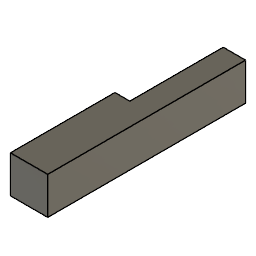
Left Fake Cross Base Beam (Autodesk Fusion 360 design; units mm, degrees)
Autodesk Fusion 360 part; units mm, degrees
sketch "Sketch1" plane through (0, 0, 0) normal (1, 0, 0) x (0, 1, 0)
  circle A0 centre (0, 0) radius 2.1971
  circle A1 centre (25.4, 0) radius 2.1971
  line L0 (10.16, 2.54) -> (15.24, 2.54)
  line L1 (15.24, 2.54) -> (15.24, -2.54)
  line L2 (15.24, -2.54) -> (10.16, -2.54)
  line L3 (10.16, -2.54) -> (10.16, 2.54)
  line L4 (-6.35, 4.7625) -> (31.75, 4.7625)
  line L5 (31.75, 4.7625) -> (31.75, -4.7625)
  line L6 (31.75, -4.7625) -> (-6.35, -4.7625)
  line L7 (-6.35, -4.7625) -> (-6.35, 4.7625)
  dimension "d1" = 25.4
  dimension "d2" = 4.3942
  dimension "d3" = 4.3942
  dimension "d4" = 5.08
  dimension "d5" = 5.08
  dimension "d6" = 2.54
  dimension "d7" = 10.16
  dimension "d8" = 9.525
  dimension "d9" = 38.1
  dimension "d10" = 4.7625
  dimension "d11" = 6.35
  constraint horizontal A0.centre A1.centre
  constraint horizontal L0
  constraint vertical L1
  constraint horizontal L2
  constraint vertical L3
  constraint coincident A0.centre origin
  constraint horizontal L4
  constraint vertical L5
  constraint horizontal L6
  constraint vertical L7
  measures "d1" distance of A0.centre A1.centre
  measures "d2" diameter of A0
  measures "d3" diameter of A1
  measures "d4" distance of L0.start L0.end
  measures "d5" distance of L0.start L2.end
  measures "d6" distance of A0.centre L0
  measures "d7" horizontal distance of A0.centre L2.end
  measures "d8" distance of L4.start L6.end
  measures "d9" distance of L4.start L4.end
  measures "d10" distance of A0.centre L4
  measures "d11" distance of A0.centre L7
extrude "Extrude1" add sketch "Sketch1" along normal blind 2.54 contours A0 | A1 | L0 L1 L2 L3 | L4 L5 L6 L7
sketch "Sketch2" plane through (2.54, 0, 0) normal (1, 0, 0) x (0, 1, 0)
  line L0 (-6.35, -4.7625) -> (31.75, -4.7625)
  line L1 (31.75, -4.7625) -> (31.75, 4.7625)
  line L2 (31.75, 4.7625) -> (-6.35, 4.7625)
  line L3 (-6.35, 4.7625) -> (-6.35, -4.7625)
  line L4 (31.75, 4.7625) -> (-6.35, 4.7625)
  line L5 (-6.35, 4.7625) -> (-6.35, -4.7625)
  line L6 (-6.35, -4.7625) -> (31.75, -4.7625)
  line L7 (31.75, -4.7625) -> (31.75, 4.7625)
  circle A0 centre (0, 0) radius 2.1971
  circle A1 centre (25.4, 0) radius 2.1971
  dimension "d14" = 4.3942
  dimension "d15" = 4.3942
  constraint horizontal L4
  constraint vertical L5
  constraint horizontal L6
  constraint vertical L7
  constraint coincident L0.start L3.end
  constraint coincident L1.end L2.start
  measures "d14" diameter of A0
  measures "d15" diameter of A1
extrude "Extrude2" add sketch "Sketch2" along normal blind 3.81 contours L0 L1 L2 L3 L4 L5 L6 L7 | A0 | A1
sketch "Sketch3" plane through (0, -6.35, 0) normal (0, -1, 0) x (1, 0, 0)
  line L0 (0, 4.7625) -> (0, -4.7625)
  line L1 (0, -4.7625) -> (6.35, -4.7625)
  line L2 (6.35, -4.7625) -> (6.35, 4.7625)
  line L3 (6.35, 4.7625) -> (0, 4.7625)
  line L4 (0, 4.7625) -> (6.35, 4.7625)
  line L5 (6.35, 4.7625) -> (6.35, -4.7625)
  line L6 (6.35, -4.7625) -> (0, -4.7625)
  line L7 (0, -4.7625) -> (0, 4.7625)
  constraint horizontal L4
  constraint vertical L5
  constraint horizontal L6
  constraint vertical L7
  constraint coincident L1.end L2.start
  constraint coincident L0.start L3.end
extrude "Extrude3" add sketch "Sketch3" along normal blind 127
sketch "Sketch4" plane through (6.35, 0, 0) normal (1, 0, 0) x (0, 1, 0)
  line L0 (31.75, -4.7625) -> (31.75, 4.7625)
  line L1 (31.75, 4.7625) -> (-133.35, 4.7625)
  line L2 (-133.35, 4.7625) -> (-133.35, -4.7625)
  line L3 (-133.35, -4.7625) -> (31.75, -4.7625)
  circle A0 centre (-47.625, 1.5875) radius 1.6
  circle A1 centre (-22.225, 1.5875) radius 1.6
  dimension "d22" = 3.2
  dimension "d23" = 3.2
  dimension "d27" = 6.35
  dimension "d62" = 25.4
  constraint horizontal A0.centre A1.centre
  measures "d22" diameter of A0
  measures "d23" diameter of A1
  measures "d27" distance of L3 A1.centre
  measures "d62" distance of A0.centre A1.centre
sketch "Sketch6" plane through (0, -133.35, 0) normal (0, -1, 0) x (1, 0, 0)
  line L0 (0, -4.7625) -> (6.35, -4.7625)
  line L1 (6.35, -4.7625) -> (6.35, 4.7625)
  line L2 (6.35, 4.7625) -> (0, 4.7625)
  line L3 (0, 4.7625) -> (0, -4.7625)
  line L4 (0, 4.7625) -> (6.35, 4.7625)
  line L5 (6.35, 4.7625) -> (6.35, -1.5875)
  line L6 (6.35, -1.5875) -> (0, -1.5875)
  line L7 (0, -1.5875) -> (0, 4.7625)
  dimension "d29" = 6.35
  dimension "d30" = 6.35
  constraint horizontal L4
  constraint vertical L5
  constraint horizontal L6
  constraint vertical L7
  constraint coincident L2.end L3.start
  measures "d29" distance of L2.end L1.end
  measures "d30" distance of L2.end L6.end
extrude "Extrude5" cut sketch "Sketch6" against normal blind 67.945 contours L0 L1 L3 L6
sketch "Sketch7" plane through (0, 0, 0) normal (-1, 0, 0) x (0, -1, 0)
  line L0 (65.405, -4.7625) -> (65.405, -1.5875)
  line L1 (65.405, -1.5875) -> (133.35, -1.5875)
  line L2 (133.35, -1.5875) -> (133.35, 4.7625)
  line L3 (133.35, 4.7625) -> (-31.75, 4.7625)
  line L4 (-31.75, 4.7625) -> (-31.75, -4.7625)
  line L5 (-31.75, -4.7625) -> (65.405, -4.7625)
  circle A0 centre (117.475, 1.5875) radius 2.1
  dimension "d33" = 4.2
  dimension "d34" = 3.175
  dimension "d35" = 15.875
  measures "d33" diameter of A0
  measures "d34" distance of L3 A0.centre
  measures "d35" distance of L2 A0.centre
extrude "Extrude6" cut sketch "Sketch7" against normal blind 6.35 contours A0
sketch "Sketch8" plane through (0, 0, 0) normal (-1, 0, 0) x (0, -1, 0)
  circle A0 centre (117.475, 1.5875) radius 2.1
  line L0 (65.405, -4.7625) -> (65.405, -1.5875)
  line L1 (65.405, -1.5875) -> (133.35, -1.5875)
  line L2 (133.35, -1.5875) -> (133.35, 4.7625)
  line L3 (133.35, 4.7625) -> (-31.75, 4.7625)
  line L4 (-31.75, 4.7625) -> (-31.75, -4.7625)
  line L5 (-31.75, -4.7625) -> (65.405, -4.7625)
  circle A1 centre (117.475, 11.4427) radius 2.1
  circle A2 centre (117.475, 11.4427) radius 3.175
  circle A3 centre (106.045, 11.4427) radius 2.1
  circle A4 centre (106.045, 11.4427) radius 3.175
  line L6 (117.475, 8.2677) -> (106.045, 8.2677)
  line L7 (117.475, 14.6177) -> (106.045, 14.6177)
  line L8 (106.045, 14.6177) -> (70.9402, 14.6177)
  line L9 (70.9402, 14.6177) -> (65.405, 6.5046)
  line L10 (106.045, 8.2677) -> (74.295, 8.2677)
  line L11 (74.295, 8.2677) -> (65.405, -4.7625)
  line L12 (65.405, 6.5046) -> (65.405, -4.7625)
  line L13 (65.405, 6.5046) -> (64.2164, 4.7625)
  line L14 (120.65, 8.2677) -> (102.87, 8.2677)
  line L15 (102.87, 8.2677) -> (102.87, 14.6177)
  line L16 (102.87, 14.6177) -> (120.65, 14.6177)
  line L17 (120.65, 14.6177) -> (120.65, 8.2677)
  dimension "d38" = 4.2
  dimension "d39" = 9.8552
  dimension "d40" = 6.35
  dimension "d45" = 4.2
  dimension "d46" = 6.35
  dimension "d47" = 11.43
  dimension "d66" = 6.35
  dimension "d68" = 31.75
  dimension "d69" = 6.35
  constraint vertical A0.centre A1.centre
  constraint concentric A1 A2
  constraint concentric A3 A4
  constraint horizontal A1.centre A3.centre
  constraint coincident A2 L6.start
  constraint coincident A4 L6.end
  constraint coincident A2 L7.start
  constraint coincident A4 L7.end
  constraint tangent A4 L7
  constraint horizontal L6
  constraint horizontal L7
  constraint parallel L7 L8
  constraint parallel L3 L10
  constraint coincident L0.start L5.end
  constraint parallel L9 L11
  constraint vertical L9.end L0.start
  constraint coincident L3 L13.end
  constraint parallel L9 L13
  constraint horizontal L14
  constraint vertical L15
  constraint horizontal L16
  constraint vertical L17
  constraint coincident L8 L15.end
  constraint coincident L10 L14.end
  constraint tangent A2 L17
  constraint tangent A4 L15
  measures "d38" diameter of A1
  measures "d39" vertical distance of A0.centre A1.centre
  measures "d40" diameter of A2
  measures "d45" diameter of A3
  measures "d46" diameter of A4
  measures "d47" distance of A1.centre A3.centre
  measures "d66" distance of L8 L10
  measures "d68" distance of L6.end L10.end
  measures "d69" distance of L9 L11
extrude "Extrude7" cut sketch "Sketch8" against normal blind 6.35 contours L0 L1 L11 L12 | L1 L2 L3 L11
extrude "Extrude8" add sketch "Sketch8" along normal blind -6.35 and the other way blind 2.54 contours L0 L1 L11 L12 | L1 L3 L11 L12 | L3 L8 L9 L10 L11 L12 L15 | L3 L12 L13 | A4 L10 L14 L15 | A4 L8 L15 L16 | A4 | A2 A4 L6 L7 L14 L16 | A2 | A2 L14 L17 | A2 L16 L17 | A1 | A3
extrude "Extrude9" add sketch "Sketch8" against normal blind 2.54 contours L0 L1 L11 L12 | A4 L10 L14 L15 | A4 L8 L15 L16 | A4 | A2 A4 L6 L7 L14 L16 | A2 | A2 L14 L17 | A2 L16 L17 | A1 | A3
sketch "Sketch10" plane through (0, 0, -4.7625) normal (0, 0, -1) x (1, 0, 0)
  line L0 (6.35, 65.405) -> (0, 65.405)
  line L1 (0, 65.405) -> (0, -31.75)
  line L2 (0, -31.75) -> (6.35, -31.75)
  line L3 (6.35, -31.75) -> (6.35, 65.405)
  line L4 (6.35, -31.75) -> (0, -31.75)
  line L5 (0, -31.75) -> (0, 65.405)
  line L6 (0, 65.405) -> (6.35, 65.405)
  line L7 (6.35, 65.405) -> (6.35, -31.75)
  constraint horizontal L4
  constraint vertical L5
  constraint horizontal L6
  constraint vertical L7
  constraint coincident L0.end L1.start
  constraint coincident L2.end L3.start
extrude "Extrude12" add sketch "Sketch10" along normal blind 0.4318
sketch "Sketch11" plane through (0, 31.75, 0) normal (0, 1, 0) x (-1, 0, 0)
  line L0 (0, -5.1943) -> (0, 4.7625)
  line L1 (0, 4.7625) -> (-6.35, 4.7625)
  line L2 (-6.35, 4.7625) -> (-6.35, -5.1943)
  line L3 (-6.35, -5.1943) -> (0, -5.1943)
  line L4 (0, -5.1943) -> (-6.35, -5.1943)
  line L5 (-6.35, -5.1943) -> (-6.35, 4.7625)
  line L6 (-6.35, 4.7625) -> (0, 4.7625)
  line L7 (0, 4.7625) -> (0, -5.1943)
  constraint horizontal L4
  constraint vertical L5
  constraint horizontal L6
  constraint vertical L7
  constraint coincident L1.end L2.start
  constraint coincident L0.start L3.end
extrude "Extrude13" add sketch "Sketch11" along normal blind 12.7
sketch "Sketch12" plane through (0, 0, 4.7625) normal (0, 0, 1) x (-1, 0, 0)
  line L0 (-2.54, 64.2164) -> (-6.35, 64.2164)
  line L1 (-6.35, 64.2164) -> (-6.35, -44.45)
  line L2 (-6.35, -44.45) -> (0, -44.45)
  line L3 (0, -44.45) -> (0, 71.9035)
  line L4 (0, 71.9035) -> (-2.54, 71.9035)
  line L5 (-2.54, 71.9035) -> (-2.54, 64.2164)
  line L6 (0, -44.45) -> (-6.35, -44.45)
  line L7 (-6.35, -44.45) -> (-6.35, 6.35)
  line L8 (-6.35, 6.35) -> (0, 6.35)
  line L9 (0, 6.35) -> (0, -44.45)
  dimension "d74" = 50.8
  constraint horizontal L6
  constraint vertical L7
  constraint horizontal L8
  constraint vertical L9
  constraint coincident L1 L7.end
  constraint coincident L2.end L3.start
  measures "d74" distance of L2.end L8.end
extrude "Extrude14" add sketch "Sketch12" along normal blind 6.35 contours L1 L2 L3 L6 L7 L8 L9
sketch "Sketch13" plane through (6.35, 0, 0) normal (1, 0, 0) x (0, 1, 0)
  line L0 (-6.35, 4.7625) -> (-64.2164, 4.7625)
  line L1 (-64.2164, 4.7625) -> (-70.9402, 14.6177)
  line L2 (-70.9402, 14.6177) -> (-120.65, 14.6177)
  line L3 (-120.65, 14.6177) -> (-120.65, 8.2677)
  line L4 (-120.65, 8.2677) -> (-74.295, 8.2677)
  line L5 (-74.295, 8.2677) -> (-65.405, -4.7625)
  line L6 (-65.405, -4.7625) -> (-65.405, -5.1943)
  line L7 (-65.405, -5.1943) -> (44.45, -5.1943)
  line L8 (44.45, -5.1943) -> (44.45, 11.1125)
  line L9 (44.45, 11.1125) -> (-6.35, 11.1125)
  line L10 (-6.35, 11.1125) -> (-6.35, 4.7625)
  line L11 (44.45, -5.1943) -> (-6.35, -5.1943)
  line L12 (-0.4841, 4.9657) -> (-6.35, -5.1943)
  line L13 (44.45, -5.1943) -> (44.45, 4.9657)
  line L14 (-0.4841, 4.9657) -> (44.45, 4.9657)
  dimension "d77" = 10.16
  dimension "d78" = 50.8
  dimension "d79" = 60
  constraint coincident L7.end L8.start
  constraint coincident L7 L11.end
  constraint coincident L8 L13.end
  constraint horizontal L14
  measures "d77" distance of L7.end L13.end
  measures "d78" distance of L7.end L11.end
  measures "d79" angle of L11 L12
extrude "Extrude15" cut sketch "Sketch13" against normal blind 6.35 contours L7 L8 L11 L12 L13 L14
fillet "Fillet1" radius 19.05 1 edges at (3.175, -6.35, 4.7625)
fillet "Fillet2" radius 6.35 1 edges at (3.175, -0.4841, 4.9657)
sketch "Sketch15" plane through (0, 44.45, 0) normal (0, 1, 0) x (-1, 0, 0)
  line L0 (-6.35, 4.9657) -> (0, 4.9657)
  line L1 (0, 4.9657) -> (0, 11.1125)
  line L2 (0, 11.1125) -> (-6.35, 11.1125)
  line L3 (-6.35, 11.1125) -> (-6.35, 4.9657)
  line L4 (34.925, 34) -> (-41.275, 34)
  line L5 (-41.275, 34) -> (-41.275, -42.2)
  line L6 (-41.275, -42.2) -> (34.925, -42.2)
  line L7 (34.925, -42.2) -> (34.925, 34)
  line L8 (34.925, 34) -> (-41.275, -42.2) construction
  line L9 (-41.275, 34) -> (34.925, -42.2) construction
  point P0 (-3.175, -4.1)
  dimension "d92" = 76.2
  dimension "d93" = 76.2
  dimension "d94" = 9.0657
  dimension "d95" = 34.925
  constraint horizontal L4
  constraint perpendicular L4 L5
  constraint parallel L4 L6
  constraint parallel L5 L7
  constraint coincident L8 P0
  constraint coincident L9 P0
  measures "d92" distance of L5.end L6.end
  measures "d93" distance of L4.end L5.end
  measures "d94" distance of L0 P0
  measures "d95" distance of L1 L7
extrude "Extrude19" cut sketch "Sketch15" against normal blind 118.745 contours L0 L1 L2 L3 | L4 L5 L6 L7
extrude "Extrude20" cut 1 faces at (3.81, -74.295, 10.3844) along direction (0, -1, 0) blind 12.7
extrude "Extrude16" [suppressed]
extrude "Extrude17" [suppressed]
sketch "Sketch14" plane through (6.35, 0, 0) normal (1, 0, 0) x (0, 1, 0)
  line L0 (-6.35, -5.1943) -> (-2.3172, 1.7907)
  arc A0 (3.1821, 4.9657) -> (-2.3172, 1.7907) centre (3.1821, -1.3843) ccw
  line L1 (3.1821, 4.9657) -> (44.45, 4.9657)
  line L2 (44.45, 4.9657) -> (44.45, 11.1125)
  line L3 (44.45, 11.1125) -> (-6.35, 11.1125)
  arc A1 (-20.549, 4.7625) -> (-6.35, 11.1125) centre (-20.549, 23.8125) ccw
  line L4 (-20.549, 4.7625) -> (-64.2164, 4.7625)
  line L5 (-64.2164, 4.7625) -> (-70.9402, 14.6177)
  line L6 (-70.9402, 14.6177) -> (-120.65, 14.6177)
  line L7 (-120.65, 14.6177) -> (-120.65, 8.2677)
  line L8 (-120.65, 8.2677) -> (-74.295, 8.2677)
  line L9 (-74.295, 8.2677) -> (-65.405, -4.7625)
  line L10 (-65.405, -4.7625) -> (-65.405, -5.1943)
  line L11 (-65.405, -5.1943) -> (-6.35, -5.1943)
  line L12 (-74.295, 8.2677) -> (-74.295, 14.6177)
  constraint coincident L8.end L9.start
  constraint coincident L6 L12.end
  constraint perpendicular L6 L12
extrude "Extrude18" [suppressed]
sketch "Sketch9" plane through (6.35, 0, 0) normal (1, 0, 0) x (0, 1, 0)
  line L0 (31.75, -5.1943) -> (31.75, 4.7625)
  line L1 (31.75, 4.7625) -> (-64.2164, 4.7625)
  line L2 (17.4625, -1.5875) -> (17.4625, -4.7625)
  line L3 (17.4625, -4.7625) -> (7.9375, -4.7625)
  line L4 (7.9375, -4.7625) -> (7.9375, -1.5875)
  line L5 (7.9375, -1.5875) -> (17.4625, -1.5875)
  line L6 (0, -2.1971) -> (7.9375, -2.1971)
  line L7 (-64.2164, 4.7625) -> (-70.9402, 14.6177)
  line L8 (-70.9402, 14.6177) -> (-120.65, 14.6177)
  line L9 (-120.65, 14.6177) -> (-120.65, 8.2677)
  line L10 (-120.65, 8.2677) -> (-74.295, 8.2677)
  line L11 (-74.295, 8.2677) -> (-65.405, -4.7625)
  line L12 (-65.405, -4.7625) -> (-65.405, -5.1943)
  line L13 (-65.405, -5.1943) -> (31.75, -5.1943)
  dimension "d55" = 9.525
  dimension "d56" = 3.175
  dimension "d57" = 7.9375
  constraint vertical L2
  constraint horizontal L3
  constraint vertical L4
  constraint perpendicular L2 L5
  constraint coincident L4 L6.end
  constraint perpendicular L4 L6
  measures "d55" distance of L4.end L2.start
  measures "d56" distance of L2.end L2.start
  measures "d57" distance of L6.start L6.end
extrude "Extrude10" [suppressed]
extrude "Extrude11" [suppressed]
equation "d7 = 0.5 in - ( 0.2 / 2 ) * 1 in"
equation "d10 = ( 0.375 / 2 ) * 1 in"
equation "d11 = ( ( 1.5 - 1 ) / 2 ) * 1 in"
equation "d39 = 0.263 in + 0.125 in"
